MOD-GRID Baseplate (Autodesk Fusion 360 design; units mm, degrees)
part number: 2026-10-21-08-43-19-319
Autodesk Fusion 360 part; units mm, degrees
sketch "Plate outline" plane through (0, 0, 0) normal (0, 0, 1) x (1, 0, 0)
  line L0 (0, 0) -> (99, 0)
  line L1 (99, 0) -> (99, 35)
  line L2 (99, 35) -> (0, 35)
  line L3 (0, 35) -> (0, 0)
  dimension "d74" = 99
  dimension "d75" = 35
  constraint coincident L0.start L3.end
  measures "d74" horizontal distance of L0.start L0.end
  measures "d75" vertical distance of L0.end L1.end
extrude "Extrude7" add sketch "Plate outline" along normal blind 3 makes body 1
fillet "Fillet3" radius 3 4 edges at (0, 35, 1.5) (99, 35, 1.5) (99, 0, 1.5) (0, 0, 1.5) on bodies 1
sketch "Hole cell" plane through (0, 0, 0) normal (0, 0, 1) x (1, 0, 0)
  line L0 (3, 3) -> (8, 3)
  line L1 (8, 3) -> (8, 8)
  line L2 (8, 8) -> (3, 8)
  line L3 (3, 8) -> (3, 3)
  dimension "d80" = 3
  dimension "d81" = 3
  dimension "d82" = 5
  dimension "d83" = 5
  measures "d80" horizontal distance of origin L0.start
  measures "d81" vertical distance of origin L0.start
  measures "d82" horizontal distance of L0.start L0.end
  measures "d83" vertical distance of L0.end L1.end
extrude "Extrude8" cut sketch "Hole cell" along normal blind 3 and the other way blind 3 bodies 1
chamfer "Chamfer5" distance 0.5 angle 45 4 edges at (5.5, 3, 0) (8, 5.5, 0) (5.5, 8, 0) (3, 5.5, 0) tangent chain off on bodies 1
pattern_linear "R-Pattern5" count 12 spacing 8 along (1, 0, 0) count 4 spacing 8 along (0, 1, 0) of "Extrude8", "Chamfer5"
chamfer "Chamfer6" distance 0.5 angle 45 8 edges at (0.8787, 0.8787, 0) (49.5, 0, 0) (98.1213, 0.8787, 0) (99, 17.5, 0) (98.1213, 34.1213, 0) (49.5, 35, 0) (0.8787, 34.1213, 0) (0, 17.5, 0) tangent chain off on bodies 1
sketch "Mouse ears" plane through (0, 0, 0) normal (0, 0, 1) x (1, 0, 0)
  circle A0 centre (-0.5355, -0.5355) radius 8
  dimension "d94" = 16
  dimension "d95" = 0.5355
  dimension "d96" = 0.5355
  measures "d94" diameter of A0
  measures "d95" horizontal distance of origin A0.centre
  measures "d96" vertical distance of origin A0.centre
extrude "Extrude9" add sketch "Mouse ears" along normal blind 0.4 separate body makes body 2
pattern_linear "R-Pattern6" count 2 spacing 100.0711 along (1, 0, 0) count 2 spacing 36.0711 along (0, 1, 0) of "Extrude9" makes body 3 at (101.1982, 1.5494, 0) makes body 4 at (0.6512, 35.5355, 0) makes body 5 at (97.9748, 37.2899, 0)
equation "grid_x = 12" comment "Cells along X - the main variable"
equation "grid_y = 4" comment "Cells along Y - the main variable"
equation "grid_pitch = 8 mm" comment "MOD-GRID pitch (measured from the official 4x12)"
equation "hole_size = 5 mm" comment "Square hole across flats (measured: 5.000)"
equation "hole_clear = 0 mm" comment "Per-side hole adjustment; raise if the connector is tight"
equation "plate_t = 3 mm" comment "Plate thickness (measured: 3.000)"
equation "border = 3 mm" comment "Edge to first hole; equals the wall between holes"
equation "corner_r = 3 mm" comment "Outer corner radius"
equation "first_layer_cham = 0.5 mm" comment "Elephant-foot chamfer on every bed-face edge"
equation "mouse_ear_r = 8 mm" comment "Mouse ear radius (ABS warp relief)"
equation "mouse_ear_t = 0.4 mm" comment "Mouse ear thickness (2 layers at 0.2 mm)"
equation "hole_w = hole_size + 2 * hole_clear" comment "Actual modelled hole width"
equation "plate_x = grid_pitch * grid_x + border" comment "Plate length (8n + 3)"
equation "plate_y = grid_pitch * grid_y + border" comment "Plate width (8n + 3)"
equation "ear_off = ( corner_r + 2 mm ) / sqrt(2) - corner_r" comment "Mouse ear centre, outside the corner arc"
equation "d74 = plate_x"
equation "d75 = plate_y"
equation "d76 = plate_t"
equation "d79 = corner_r"
equation "d80 = border"
equation "d81 = border"
equation "d82 = hole_w"
equation "d83 = hole_w"
equation "d84 = plate_t"
equation "d86 = plate_t"
equation "d88 = first_layer_cham"
equation "d89 = grid_x"
equation "d90 = grid_y"
equation "d91 = grid_pitch"
equation "d92 = grid_pitch"
equation "d93 = first_layer_cham"
equation "d94 = mouse_ear_r * 2"
equation "d95 = ear_off"
equation "d96 = ear_off"
equation "d97 = mouse_ear_t"
equation "d101 = plate_x + 2 * ear_off"
equation "d102 = plate_y + 2 * ear_off"
named bodies: "Baseplate", "Support - Mouse Ear 1", "Support - Mouse Ear 2", "Support - Mouse Ear 3", "Support - Mouse Ear 4"
